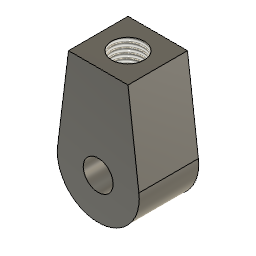
swival (Autodesk Fusion 360 design; units mm, degrees)
part number: 2026-08-20-13-28-36-642
Autodesk Fusion 360 part; units mm, degrees
sketch "Sketch1" plane through (0, 0, 0) normal (0, 1, 0) x (1, 0, 0)
  line L0 (0, 0) -> (0, -50)
  line L1 (0, -50) -> (16, -50)
  line L2 (0, -50) -> (-16, -50)
  line L3 (-16, -50) -> (-21.8346, -2.6929)
  line L4 (16, -50) -> (21.8346, -2.6929)
  circle A0 centre (0, 0) radius 8
  arc A1 (21.8346, -2.6929) -> (-21.8346, -2.6929) centre (0, 0) ccw
  dimension "d2" = 50
  dimension "d3" = 16
  dimension "d4" = 16
  dimension "d5" = 44
  dimension "d6" = 16
  constraint vertical L0
  constraint perpendicular L0 L1
  constraint perpendicular L0 L2
  constraint coincident L0.start A0.centre
  constraint tangent L4 A1
  constraint tangent L3 A1
  measures "d2" distance of L0.start L0.end
  measures "d3" distance of L0.end L1.end
  measures "d4" distance of L0.end L2.end
  measures "d5" diameter of A1
  measures "d6" diameter of A0
extrude "Extrude1" add sketch "Sketch1" along normal blind 32
hole "Hole1" at (0, 16, 50) direction (0, 0, -1) diameter 17.519 depth 32 tip angle 118
thread "Thread1" "ISO Metric profile 20.0 M20x2.5 M20x2.5 6H" thread offset 0 thread depth 7.4
